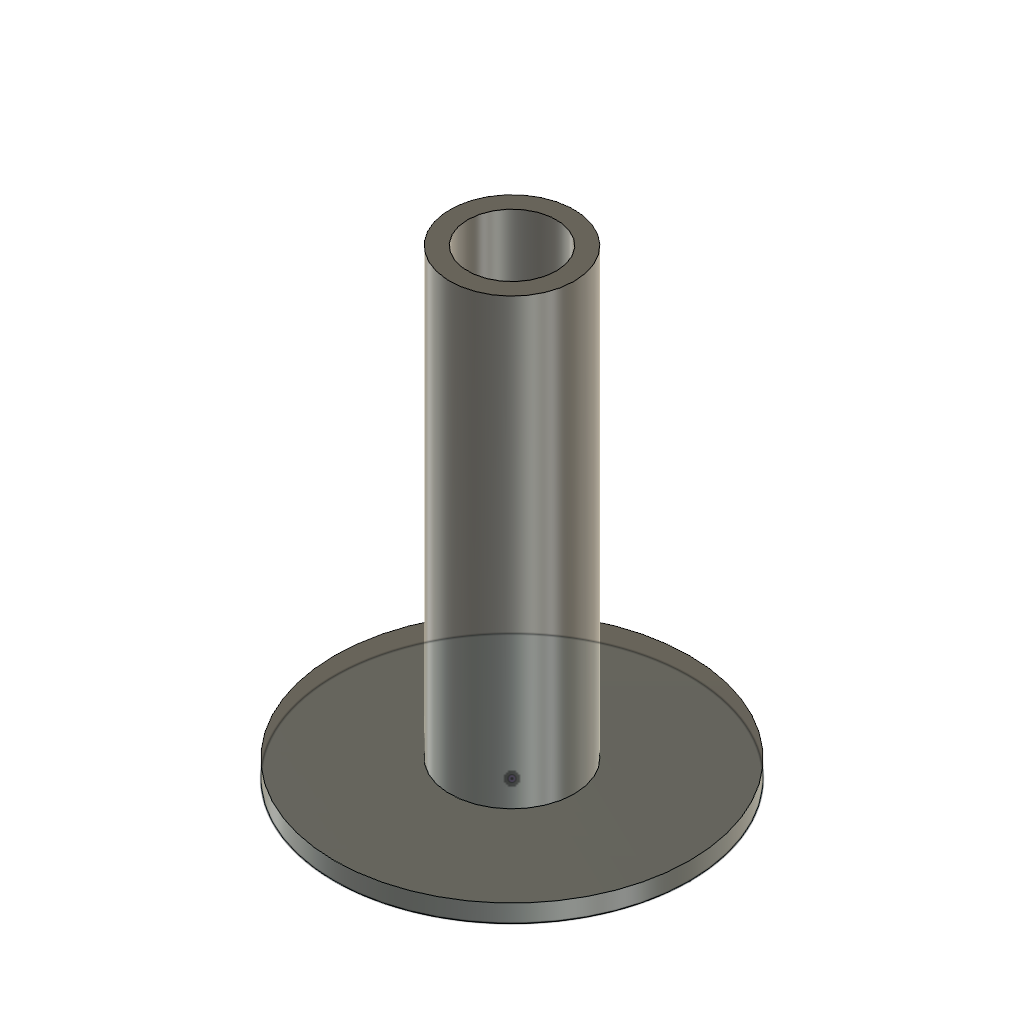
barrel_fastener_25mm (Autodesk Fusion 360 design; units mm, degrees)
part number: 2026-10-03-18-41-39-812
Autodesk Fusion 360 part; units mm, degrees
sketch "Sketch1" plane through (0, 0, 0) normal (0, 0, 1) x (1, 0, 0)
  circle A0 centre (0, 0) radius 10
  dimension "d1" = 20
  constraint coincident A0.centre origin
  measures "d1" diameter of A0
extrude "Extrude1" add sketch "Sketch1" along normal blind 1
sketch "Sketch3" plane through (0, 0, 1) normal (0, 0, 1) x (-1, 0, 0)
  circle A0 centre (0, 0) radius 10
  circle A1 centre (0, 0) radius 2.5
  circle A2 centre (0, 0) radius 3.5
  dimension "d9" = 5
  dimension "d10" = 7
  constraint coincident A0.centre A1.centre
  constraint concentric A1 A2
  measures "d9" diameter of A1
  measures "d10" diameter of A2
extrude "Extrude3" add sketch "Sketch3" along normal blind 25 contours A2
